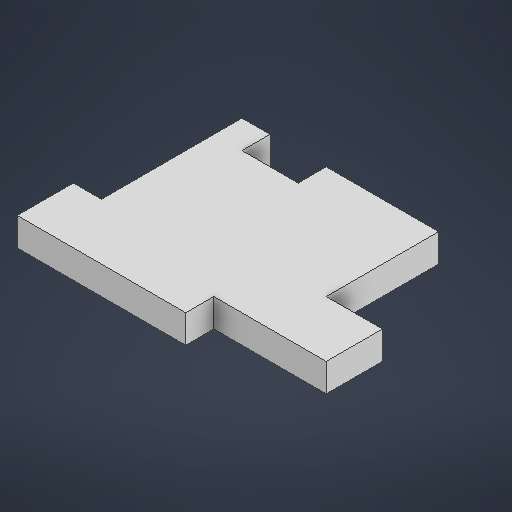
# Autodesk Inventor part: partTWO
Saved by Autodesk Inventor 2027 (Build 310192060, 192F)
## iProperties
Created: 2026-10-28
Part Number: partTWO
Material: Generic
Document SubType Name: Modeling
Designer: 6100673
Density: 1 g/cm^3
Appearance: Default
Author: 6100673
Autodesk Inventor part; units mm, degrees
ref_plane "YZ Plane" through (0, 0, 0) normal (1, 0, 0) x (0, 1, 0)
ref_plane "XZ Plane" through (0, 0, 0) normal (0, 1, 0) x (-1, 0, 0)
ref_plane "XY Plane" through (0, 0, 0) normal (0, 0, 1) x (1, 0, 0)
sketch "Sketch8" plane through (0, 0, 0) normal (0, 1, 0) x (-1, 0, 0)
  line L0 (0, 0) -> (-60, 0)
  line L1 (-60, 0) -> (-60, -10)
  line L2 (-60, -10) -> (-100, -10)
  line L3 (-100, -10) -> (-100, -30)
  line L4 (-100, -30) -> (-80, -30)
  line L5 (-80, -30) -> (-80, -70)
  line L6 (-80, -70) -> (-40, -70)
  line L7 (-40, -70) -> (-40, -60)
  line L8 (-40, -60) -> (-20, -60)
  line L9 (-20, -60) -> (-20, -70)
  line L10 (-20, -70) -> (-10, -70)
  line L11 (-10, -70) -> (-10, -20)
  line L12 (-10, -20) -> (0, -20)
  line L13 (0, -20) -> (0, 0)
  dimension "d8" = 60
  dimension "d9" = 10
  dimension "d10" = 40
  dimension "d11" = 20
  dimension "d12" = 20
  dimension "d13" = 40
  dimension "d14" = 40
  dimension "d15" = 10
  dimension "d16" = 20
  dimension "d17" = 10
  dimension "d18" = 10
  dimension "d19" = 50
  constraints: 28 end point, 11 perpendicular, 2 point on line, 1 horizontal
  measures "d8" distance of L0.start L0.end
  measures "d9" distance of L0.end L1.end
  measures "d10" distance of L1.end L2.end
  measures "d11" distance of L2.end L3.end
  measures "d12" distance of L3.end L4.end
  measures "d13" distance of L4.end L5.end
  measures "d14" distance of L5.end L6.end
  measures "d15" distance of L6.end L7.end
  measures "d16" distance of L7.end L8.end
  measures "d17" distance of L8.end L9.end
  measures "d18" distance of L9.end L10.end
  measures "d19" distance of L10.end L11.end
extrude "Extrusion1" add sketch "Sketch8" along normal blind 10
body "Solid3"
